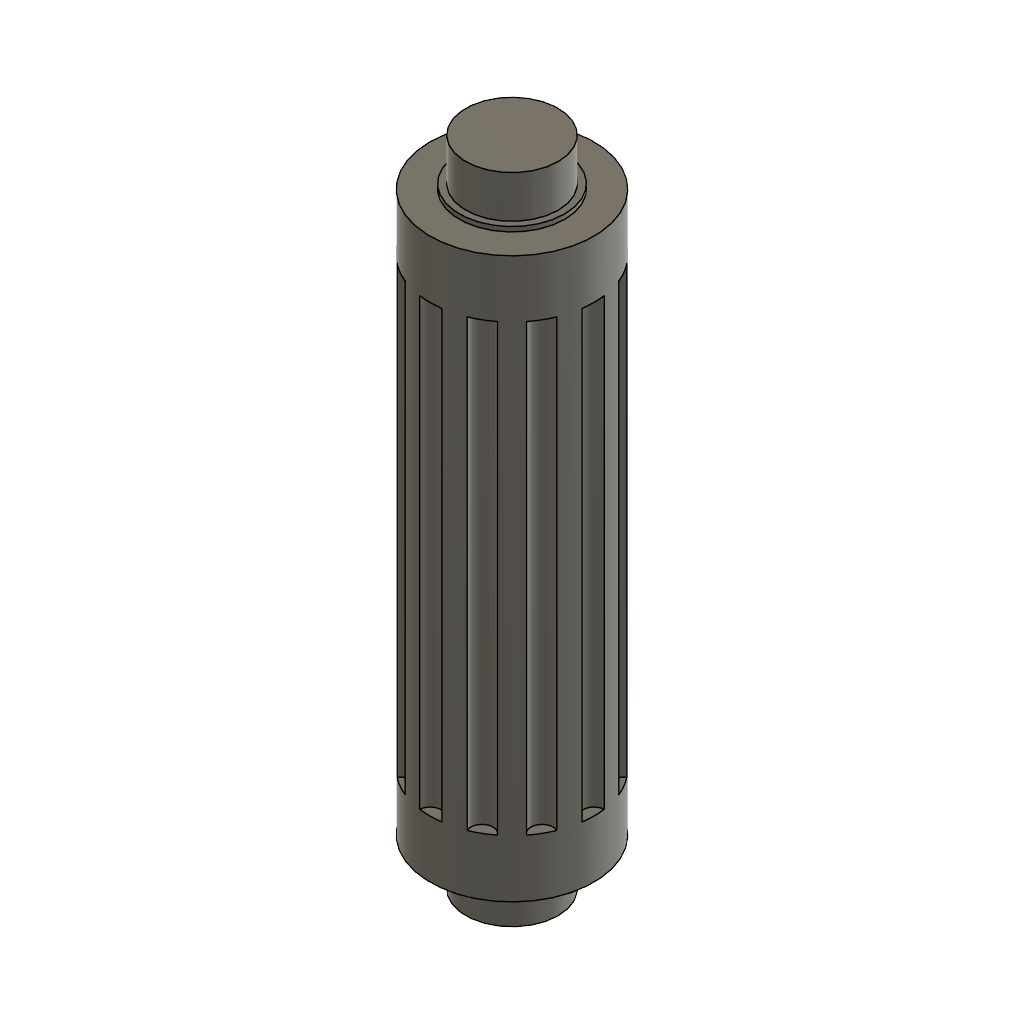
02-00_컨베이어_조립품 (Autodesk Fusion 360 archive; units mm, degrees)
design "아이들롤러"
Autodesk Fusion 360 part; units mm, degrees
(part 1 of 2)
sketch "스케치1" plane through (0, 0, 0) normal (0, 1, 0) x (1, 0, 0)
  circle A0 centre (0, 0) radius 7
  dimension "d1" = 14
  constraint coincident A0.centre origin
  measures "d1" diameter of A0
extrude "돌출1" add sketch "스케치1" along normal blind 47.8
sketch "스케치2" plane through (0, 47.8, 0) normal (0, 1, 0) x (-1, 0, 0)
  circle A0 centre (0, 0) radius 7
  circle A1 centre (0, 0) radius 4.5
  dimension "d4" = 9
  constraint coincident A0.centre A1.centre
  measures "d4" diameter of A1
extrude "돌출2" add sketch "스케치2" along normal blind 0.4 contours A1
sketch "스케치3" plane through (0, 48.2, 0) normal (0, 1, 0) x (-1, 0, 0)
  circle A0 centre (0, 0) radius 4.5
  circle A1 centre (0, 0) radius 3.95
  dimension "d7" = 7.9
  constraint coincident A0.centre A1.centre
  measures "d7" diameter of A1
extrude "돌출3" add sketch "스케치3" along normal blind 3.6 contours A1
sketch "스케치4" plane through (0, 0, 0) normal (0, -1, 0) x (1, 0, 0)
  circle A0 centre (0, 0) radius 7
  circle A1 centre (0, 0) radius 4.5
  dimension "d10" = 9
  constraint concentric A0 A1
  measures "d10" diameter of A1
extrude "돌출4" add sketch "스케치4" along normal blind 0.4 contours A1
sketch "스케치5" plane through (0, -0.4, 0) normal (0, -1, 0) x (1, 0, 0)
  circle A0 centre (0, 0) radius 4.5
  circle A1 centre (0, 0) radius 3.95
  dimension "d13" = 7.9
  constraint coincident A0.centre A1.centre
  measures "d13" diameter of A1
extrude "돌출5" add sketch "스케치5" along normal blind 3.6 contours A1
ref_plane "작업 평면1" through (0, 4.9, 0) normal (0, -1, 0) x (-1, 0, 0)
sketch "스케치6" plane through (0, 4.9, 0) normal (0, -1, 0) x (-1, 0, 0)
  circle A0 centre (-7, 0) radius 0.95
  circle A1 centre (-6.0622, -3.5) radius 0.95
  circle A2 centre (-3.5, -6.0622) radius 0.95
  circle A3 centre (0, -7) radius 0.95
  circle A4 centre (3.5, -6.0622) radius 0.95
  circle A5 centre (6.0622, -3.5) radius 0.95
  circle A6 centre (7, 0) radius 0.95
  circle A7 centre (6.0622, 3.5) radius 0.95
  circle A8 centre (3.5, 6.0622) radius 0.95
  circle A9 centre (0, 7) radius 0.95
  circle A10 centre (-3.5, 6.0622) radius 0.95
  circle A11 centre (-6.0622, 3.5) radius 0.95
  dimension "d18" = 1.9
  dimension "d20" = 360
  measures "d18" diameter of A0
extrude "돌출6" cut sketch "스케치6" against normal blind 38

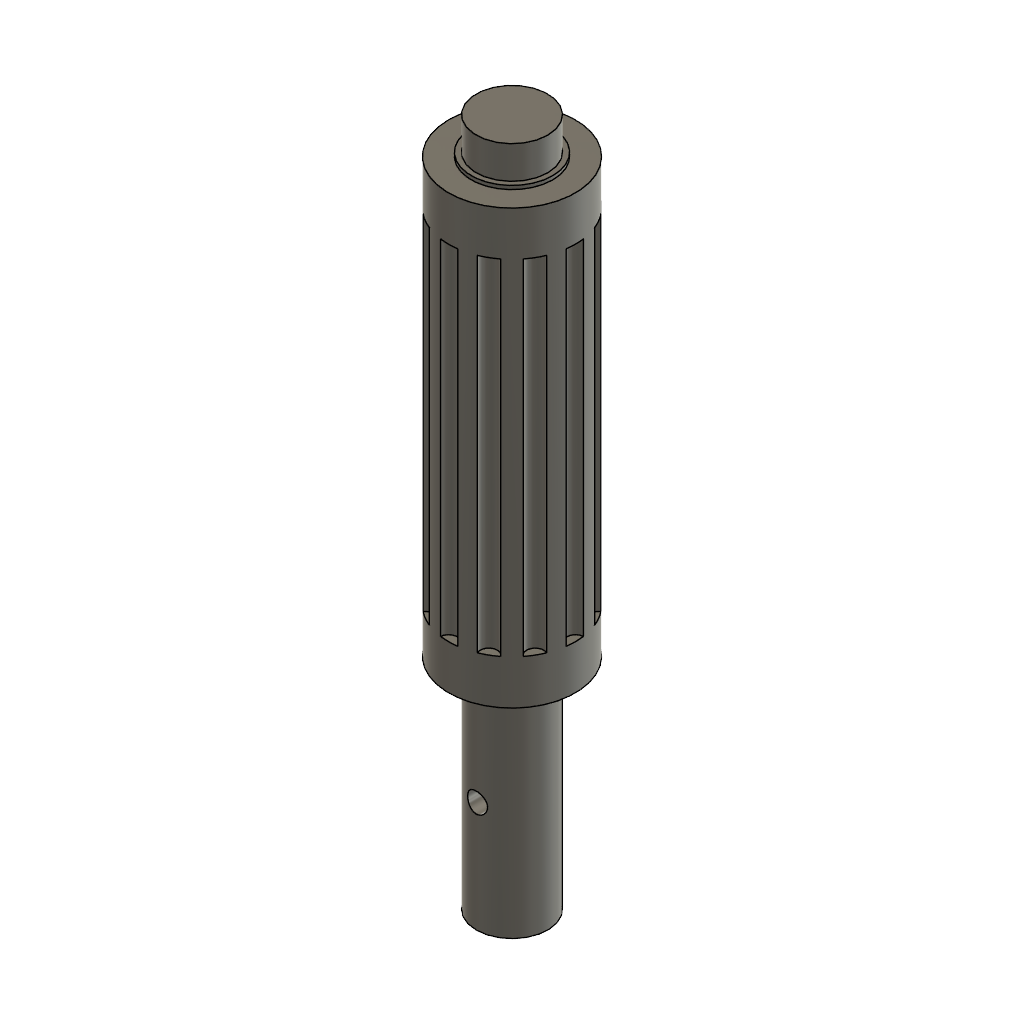
design "구동롤러"
Autodesk Fusion 360 part; units mm, degrees
sketch "스케치1" plane through (0, 0, 0) normal (0, 1, 0) x (1, 0, 0)
  circle A0 centre (0, 0) radius 7
  dimension "d1" = 14
  constraint coincident A0.centre origin
  measures "d1" diameter of A0
extrude "돌출1" add sketch "스케치1" along normal blind 47.8
sketch "스케치2" plane through (0, 47.8, 0) normal (0, 1, 0) x (-1, 0, 0)
  circle A0 centre (0, 0) radius 7
  circle A1 centre (0, 0) radius 4.5
  dimension "d4" = 9
  constraint coincident A0.centre A1.centre
  measures "d4" diameter of A1
extrude "돌출2" add sketch "스케치2" along normal blind 0.4 contours A1
sketch "스케치3" plane through (0, 0, 0) normal (0, -1, 0) x (1, 0, 0)
  circle A0 centre (0, 0) radius 7
  circle A1 centre (0, 0) radius 4.5
  dimension "d7" = 9
  constraint concentric A0 A1
  measures "d7" diameter of A1
extrude "돌출3" add sketch "스케치3" along normal blind 0.4 contours A1
sketch "스케치4" plane through (0, -0.4, 0) normal (0, -1, 0) x (1, 0, 0)
  circle A0 centre (0, 0) radius 4.5
  circle A1 centre (0, 0) radius 3.95
  dimension "d10" = 7.9
  constraint concentric A0 A1
  measures "d10" diameter of A1
extrude "돌출4" add sketch "스케치4" along normal blind 23.8 contours A1
sketch "스케치5" plane through (0, 48.2, 0) normal (0, 1, 0) x (-1, 0, 0)
  circle A0 centre (0, 0) radius 4.5
  circle A1 centre (0, 0) radius 3.95
  dimension "d13" = 7.9
  constraint concentric A0 A1
  measures "d13" diameter of A1
extrude "돌출5" add sketch "스케치5" along normal blind 3.6 contours A1
ref_plane "작업 평면1" through (0, 42.9, 0) normal (0, 1, 0) x (1, 0, 0)
sketch "스케치6" plane through (0, 42.9, 0) normal (0, 1, 0) x (1, 0, 0)
  circle A0 centre (7, 0) radius 0.95
  circle A1 centre (6.0622, 3.5) radius 0.95
  circle A2 centre (3.5, 6.0622) radius 0.95
  circle A3 centre (0, 7) radius 0.95
  circle A4 centre (-3.5, 6.0622) radius 0.95
  circle A5 centre (-6.0622, 3.5) radius 0.95
  circle A6 centre (-7, 0) radius 0.95
  circle A7 centre (-6.0622, -3.5) radius 0.95
  circle A8 centre (-3.5, -6.0622) radius 0.95
  circle A9 centre (0, -7) radius 0.95
  circle A10 centre (3.5, -6.0622) radius 0.95
  circle A11 centre (6.0622, -3.5) radius 0.95
  dimension "d18" = 1.9
  dimension "d20" = 360
  measures "d18" diameter of A0
extrude "돌출6" cut sketch "스케치6" against normal blind 38
sketch "스케치7" plane through (0, -24.2, 0) normal (0, -1, 0) x (1, 0, 0)
  circle A0 centre (0, 0) radius 3.95
  line L0 (2.5695, -3) -> (-2.5695, -3)
  dimension "d23" = 3
  constraint coincident A0 L0.start
  constraint coincident A0 L0.end
  constraint horizontal L0
  measures "d23" distance of A0.centre L0
extrude "돌출7" cut sketch "스케치7" against normal blind 23.8 contours A0 L0 picked at (0.7068, -3.1109)
sketch "스케치8" plane through (0, 0, -3) normal (0, 0, -1) x (-1, 0, 0)
  line L0 (-2.5695, -24.2) -> (2.5695, -24.2)
  line L1 (2.5695, -24.2) -> (2.5695, -0.4)
  line L2 (2.5695, -0.4) -> (-2.5695, -0.4)
  line L3 (-2.5695, -0.4) -> (-2.5695, -24.2)
  circle A0 centre (0, -12) radius 1.1
  dimension "d26" = 2.2
  dimension "d27" = 12.2
  measures "d26" diameter of A0
  measures "d27" distance of L0 A0.centre
extrude "돌출8" cut sketch "스케치8" against normal blind 7 contours A0

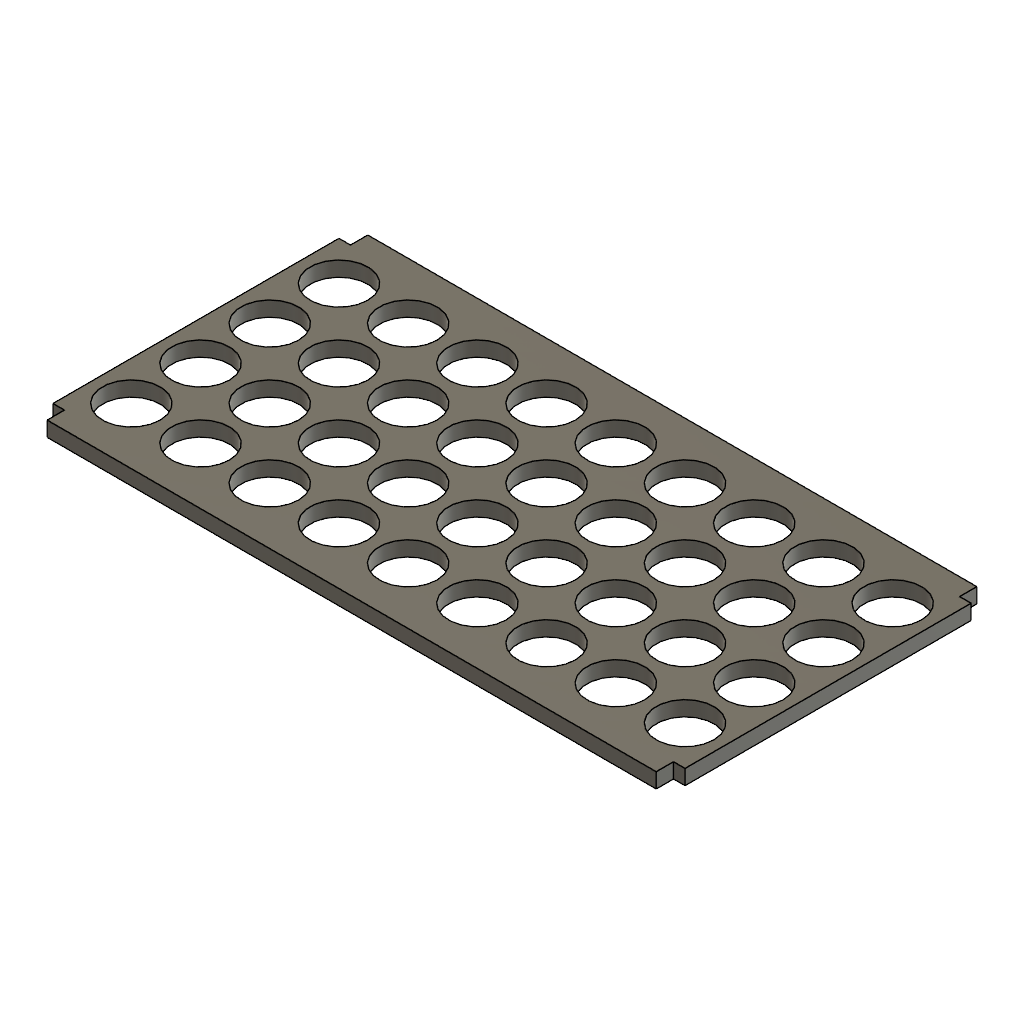
design "받침판"
Autodesk Fusion 360 part; units mm, degrees
sketch "스케치1" plane through (0, 0, 0) normal (0, 1, 0) x (1, 0, 0)
  line L0 (-54.8, 27.8) -> (54.8, 27.8)
  line L1 (54.8, 27.8) -> (54.8, -27.8)
  line L2 (54.8, -27.8) -> (-54.8, -27.8)
  line L3 (-54.8, -27.8) -> (-54.8, 27.8)
  line L4 (0, 27.8) -> (0, -27.8) construction
  line L5 (-54.8, 0) -> (54.8, 0) construction
  dimension "d1" = 109.6
  dimension "d3" = 55.6
  constraint horizontal L0
  constraint vertical L1
  constraint horizontal L2
  constraint vertical L3
  constraint midpoint L0 L4.start
  constraint midpoint L2 L4.end
  constraint midpoint L3 L5.start
  constraint midpoint L1 L5.end
  constraint coincident origin L4
  constraint coincident origin L5
  measures "d1" distance of L0.start L0.end
  measures "d3" distance of L0.end L1.end
extrude "돌출1" add sketch "스케치1" along normal blind 2.6
sketch "스케치2" plane through (0, 2.6, 0) normal (0, 1, 0) x (-1, 0, 0)
  line L0 (54.8, 27.8) -> (-54.8, 27.8)
  line L1 (-54.8, 27.8) -> (-54.8, -27.8)
  line L2 (-54.8, -27.8) -> (54.8, -27.8)
  line L3 (54.8, -27.8) -> (54.8, 27.8)
  line L4 (-54.8, -27.8) -> (-52.8, -27.8)
  line L5 (-52.8, -27.8) -> (-52.8, -24.8)
  line L6 (-52.8, -24.8) -> (-54.8, -24.8)
  line L7 (-54.8, -24.8) -> (-54.8, -27.8)
  line L8 (-54.8, 27.8) -> (-52.8, 27.8)
  line L9 (-52.8, 27.8) -> (-52.8, 24.8)
  line L10 (-52.8, 24.8) -> (-54.8, 24.8)
  line L11 (-54.8, 24.8) -> (-54.8, 27.8)
  line L12 (54.8, 27.8) -> (52.8, 27.8)
  line L13 (52.8, 27.8) -> (52.8, 24.8)
  line L14 (52.8, 24.8) -> (54.8, 24.8)
  line L15 (54.8, 24.8) -> (54.8, 27.8)
  line L16 (54.8, -27.8) -> (52.8, -27.8)
  line L17 (52.8, -27.8) -> (52.8, -24.8)
  line L18 (52.8, -24.8) -> (54.8, -24.8)
  line L19 (54.8, -24.8) -> (54.8, -27.8)
  dimension "d6" = 2
  dimension "d7" = 3
  dimension "d8" = 2
  dimension "d9" = 3
  dimension "d10" = 2
  dimension "d11" = 3
  dimension "d12" = 2
  dimension "d13" = 3
  constraint horizontal L4
  constraint vertical L5
  constraint horizontal L6
  constraint vertical L7
  constraint coincident L1.end L2.start
  constraint horizontal L8
  constraint vertical L9
  constraint horizontal L10
  constraint vertical L11
  constraint coincident L0.end L1.start
  constraint horizontal L12
  constraint vertical L13
  constraint horizontal L14
  constraint vertical L15
  constraint coincident L0.start L3.end
  constraint horizontal L16
  constraint vertical L17
  constraint horizontal L18
  constraint vertical L19
  constraint coincident L2.end L3.start
  measures "d6" distance of L1.end L4.end
  measures "d7" distance of L1.end L6.end
  measures "d8" distance of L0.end L8.end
  measures "d9" distance of L0.end L10.end
  measures "d10" distance of L0.start L12.end
  measures "d11" distance of L0.start L14.end
  measures "d12" distance of L2.end L16.end
  measures "d13" distance of L2.end L18.end
extrude "돌출2" cut sketch "스케치2" against normal blind 2.6 contours L0 L3 L12 L13 L14 L15 | L0 L1 L8 L9 L10 L11 | L2 L3 L16 L17 L18 L19 | L1 L2 L4 L5 L6 L7
sketch "스케치3" plane through (0, 2.6, 0) normal (0, 1, 0) x (-1, 0, 0)
  line L0 (52.8, -27.8) -> (52.8, -24.8)
  line L1 (52.8, -24.8) -> (54.8, -24.8)
  line L2 (54.8, -24.8) -> (54.8, 24.8)
  line L3 (54.8, 24.8) -> (52.8, 24.8)
  line L4 (52.8, 24.8) -> (52.8, 27.8)
  line L5 (52.8, 27.8) -> (-52.8, 27.8)
  line L6 (-52.8, 27.8) -> (-52.8, 24.8)
  line L7 (-52.8, 24.8) -> (-54.8, 24.8)
  line L8 (-54.8, 24.8) -> (-54.8, -24.8)
  line L9 (-54.8, -24.8) -> (-52.8, -24.8)
  line L10 (-52.8, -24.8) -> (-52.8, -27.8)
  line L11 (-52.8, -27.8) -> (52.8, -27.8)
  circle A0 centre (-48, -18) radius 5
  circle A1 centre (-36, -18) radius 5
  circle A2 centre (-24, -18) radius 5
  circle A3 centre (-12, -18) radius 5
  circle A4 centre (0, -18) radius 5
  circle A5 centre (12, -18) radius 5
  circle A6 centre (24, -18) radius 5
  circle A7 centre (36, -18) radius 5
  circle A8 centre (48, -18) radius 5
  circle A9 centre (-48, -6) radius 5
  circle A10 centre (-36, -6) radius 5
  circle A11 centre (-24, -6) radius 5
  circle A12 centre (-12, -6) radius 5
  circle A13 centre (0, -6) radius 5
  circle A14 centre (12, -6) radius 5
  circle A15 centre (24, -6) radius 5
  circle A16 centre (36, -6) radius 5
  circle A17 centre (48, -6) radius 5
  circle A18 centre (-48, 6) radius 5
  circle A19 centre (-36, 6) radius 5
  circle A20 centre (-24, 6) radius 5
  circle A21 centre (-12, 6) radius 5
  circle A22 centre (0, 6) radius 5
  circle A23 centre (12, 6) radius 5
  circle A24 centre (24, 6) radius 5
  circle A25 centre (36, 6) radius 5
  circle A26 centre (48, 6) radius 5
  circle A27 centre (-48, 18) radius 5
  circle A28 centre (-36, 18) radius 5
  circle A29 centre (-24, 18) radius 5
  circle A30 centre (-12, 18) radius 5
  circle A31 centre (0, 18) radius 5
  circle A32 centre (12, 18) radius 5
  circle A33 centre (24, 18) radius 5
  circle A34 centre (36, 18) radius 5
  circle A35 centre (48, 18) radius 5
  dimension "d16" = 10
  dimension "d19" = 96
  dimension "d20" = 36
  dimension "d21" = 6.8
  dimension "d22" = 9.8
  measures "d16" diameter of A0
  measures "d21" distance of L8 A0.centre
  measures "d22" distance of L11 A0.centre
extrude "돌출3" cut sketch "스케치3" against normal blind 2.6 contours A0 | A1 | A2 | A3 | A4 | A5 | A6 | A7 | A8 | A9 | A10 | A11 | A12 | A13 | A14 | A15 | A16 | A17 | A18 | A19 | A20 | A21 | A22 | A23 | A24 | A25 | A26 | A27 | A28 | A29 | A30 | A31 | A32 | A33 | A34 | A35

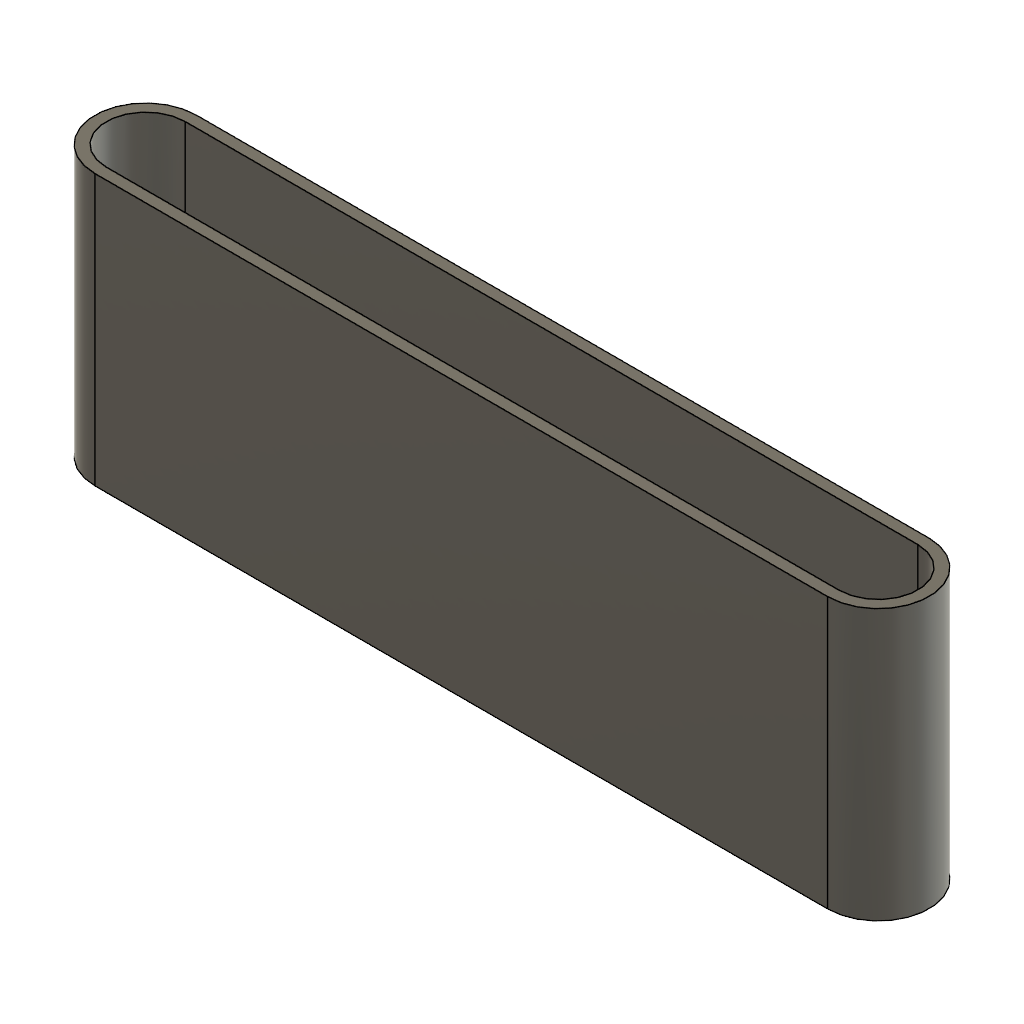
design "벨트"
Autodesk Fusion 360 part; units mm, degrees
sketch "스케치1" plane through (0, 0, 0) normal (0, 1, 0) x (1, 0, 0)
  line L0 (-65, -9) -> (65, -9)
  arc A0 (65, -9) -> (65, 9) centre (65, 0) ccw
  line L1 (65, 9) -> (-65, 9)
  arc A1 (-65, 9) -> (-65, -9) centre (-65, 0) ccw
  line L2 (-65, 0) -> (65, 0) construction
  line L3 (-65, -7) -> (65, -7)
  arc A2 (65, -7) -> (65, 7) centre (65, 0) ccw
  line L4 (65, 7) -> (-65, 7)
  arc A3 (-65, 7) -> (-65, -7) centre (-65, 0) ccw
  line L5 (-65, 0) -> (65, 0) construction
  dimension "d1" = 18
  dimension "d2" = 14
  constraint tangent L0 A0
  constraint tangent A0 L1
  constraint parallel L0 L1
  constraint tangent L1 A1
  constraint tangent L0 A1
  constraint horizontal L2
  constraint midpoint origin L2
  constraint tangent L3 A2
  constraint tangent A2 L4
  constraint parallel L3 L4
  constraint tangent L4 A3
  constraint tangent L3 A3
  constraint coincident A0.centre L2.end
  constraint parallel L2 L5
  constraint coincident A1.centre L2.start
  measures "d1" diameter of A0
  measures "d2" diameter of A2
extrude "돌출1" add sketch "스케치1" along normal blind 48

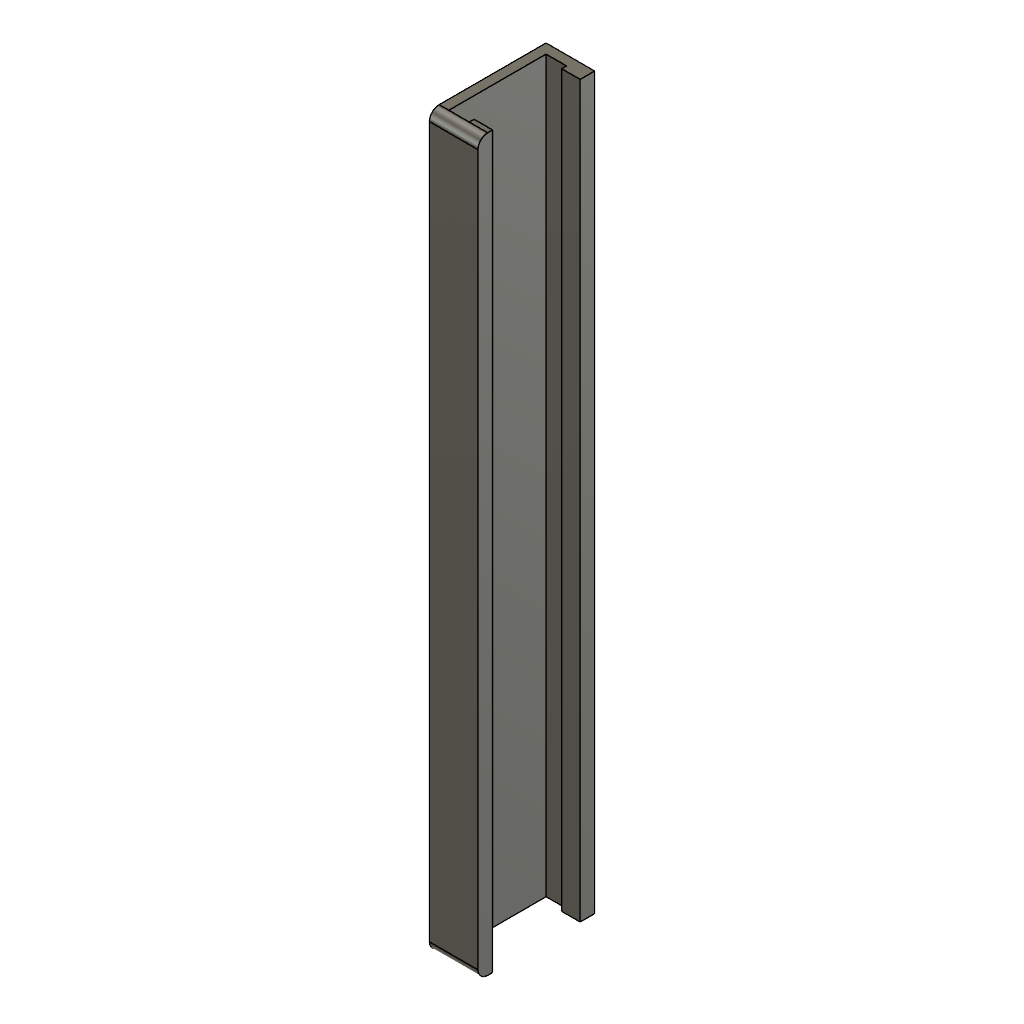
design "케이블커버"
Autodesk Fusion 360 part; units mm, degrees
sketch "스케치1" plane through (0, 0, 0) normal (0, 1, 0) x (1, 0, 0)
  line L0 (0, 0) -> (-10, 0)
  line L1 (-10, 0) -> (-10, 24)
  line L2 (-10, 24) -> (0, 24)
  line L3 (0, 24) -> (0, 21)
  line L4 (0, 21) -> (-3.8, 21)
  line L5 (-3.8, 21) -> (-3.8, 22)
  line L6 (-3.8, 22) -> (-8, 22)
  line L7 (-10, 12) -> (0, 12) construction
  line L8 (0, 0) -> (0, 3)
  line L9 (-3.8, 3) -> (-3.8, 2)
  line L10 (-3.8, 2) -> (-8, 2)
  line L11 (0, 3) -> (-3.8, 3)
  line L12 (-8, 22) -> (-8, 2)
  dimension "d1" = 10
  dimension "d2" = 24
  dimension "d3" = 3
  dimension "d4" = 3.8
  dimension "d5" = 1
  constraint coincident L0.start L8.start
  constraint horizontal L0
  constraint perpendicular L0 L1
  constraint perpendicular L1 L2
  constraint perpendicular L2 L3
  constraint perpendicular L3 L4
  constraint perpendicular L2 L5
  constraint perpendicular L5 L6
  constraint midpoint L1 L7.start
  constraint perpendicular L1 L7
  constraint symmetric L2.end L7 L0.start
  constraint symmetric L3.end L7 L8.end
  constraint symmetric L4.end L7 L9.start
  constraint symmetric L5.end L7 L9.end
  constraint symmetric L6.end L7 L10.end
  measures "d1" distance of L0.start L0.end
  measures "d2" distance of L0.end L1.end
  measures "d3" distance of L2.end L3.end
  measures "d4" distance of L3.end L4.end
  measures "d5" distance of L4.end L5.end
extrude "돌출1" add sketch "스케치1" along normal blind 150
fillet "필렛1" radius 2 2 edges at (-5, 150, 0) (-5, 0, 0)

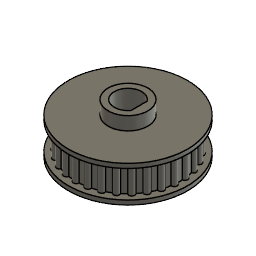
design "풀리_모터"
Autodesk Fusion 360 part; units mm, degrees
sketch "스케치1" plane through (0, 0, 0) normal (0, 1, 0) x (1, 0, 0)
  circle A0 centre (0, 0) radius 13.5
  dimension "d1" = 27
  constraint coincident A0.centre origin
  measures "d1" diameter of A0
extrude "돌출1" add sketch "스케치1" along normal blind 1
sketch "스케치2" plane through (0, 1, 0) normal (0, 1, 0) x (-1, 0, 0)
  circle A0 centre (0, 0) radius 13.5
  arc A1 (6.3702, -9.8733) -> (7.4216, -9.1095) centre (6.9065, -9.5059) ccw
  arc A2 (4.1783, -10.982) -> (5.3654, -10.4535) centre (4.7792, -10.7342) ccw
  arc A3 (1.8037, -11.6107) -> (3.0748, -11.3406) centre (2.443, -11.4932) ccw
  arc A4 (-0.6498, -11.732) -> (0.6498, -11.732) centre (0, -11.75) ccw
  arc A5 (-3.0748, -11.3406) -> (-1.8037, -11.6107) centre (-2.443, -11.4932) ccw
  arc A6 (-5.3654, -10.4535) -> (-4.1783, -10.982) centre (-4.7792, -10.7342) ccw
  arc A7 (-7.4216, -9.1095) -> (-6.3702, -9.8733) centre (-6.9065, -9.5059) ccw
  arc A8 (-9.1534, -7.3674) -> (-8.2838, -8.3331) centre (-8.732, -7.8623) ccw
  arc A9 (-10.4851, -5.3033) -> (-9.8354, -6.4287) centre (-10.1758, -5.875) ccw
  arc A10 (-11.3586, -3.0074) -> (-10.957, -4.2433) centre (-11.1749, -3.6309) ccw
  arc A11 (-11.7357, -0.5801) -> (-11.5998, -1.8725) centre (-11.6856, -1.2282) ccw
  arc A12 (-11.5998, 1.8725) -> (-11.7357, 0.5801) centre (-11.6856, 1.2282) ccw
  arc A13 (-10.957, 4.2433) -> (-11.3586, 3.0074) centre (-11.1749, 3.6309) ccw
  arc A14 (-9.8354, 6.4287) -> (-10.4851, 5.3033) centre (-10.1758, 5.875) ccw
  arc A15 (-8.2838, 8.3331) -> (-9.1534, 7.3674) centre (-8.732, 7.8623) ccw
  arc A16 (-6.3702, 9.8733) -> (-7.4216, 9.1095) centre (-6.9065, 9.5059) ccw
  arc A17 (-4.1783, 10.982) -> (-5.3654, 10.4535) centre (-4.7792, 10.7342) ccw
  arc A18 (-1.8037, 11.6107) -> (-3.0748, 11.3406) centre (-2.443, 11.4932) ccw
  arc A19 (0.6498, 11.732) -> (-0.6498, 11.732) centre (0, 11.75) ccw
  arc A20 (3.0748, 11.3406) -> (1.8037, 11.6107) centre (2.443, 11.4932) ccw
  arc A21 (5.3654, 10.4535) -> (4.1783, 10.982) centre (4.7792, 10.7342) ccw
  arc A22 (7.4216, 9.1095) -> (6.3702, 9.8733) centre (6.9065, 9.5059) ccw
  arc A23 (9.1534, 7.3674) -> (8.2838, 8.3331) centre (8.732, 7.8623) ccw
  arc A24 (10.4851, 5.3033) -> (9.8354, 6.4287) centre (10.1758, 5.875) ccw
  arc A25 (11.3586, 3.0074) -> (10.957, 4.2433) centre (11.1749, 3.6309) ccw
  arc A26 (11.7357, 0.5801) -> (11.5998, 1.8725) centre (11.6856, 1.2282) ccw
  arc A27 (11.5998, -1.8725) -> (11.7357, -0.5801) centre (11.6856, -1.2282) ccw
  arc A28 (10.957, -4.2433) -> (11.3586, -3.0074) centre (11.1749, -3.6309) ccw
  arc A29 (9.8354, -6.4287) -> (10.4851, -5.3033) centre (10.1758, -5.875) ccw
  arc A30 (8.2838, -8.3331) -> (9.1534, -7.3674) centre (8.732, -7.8623) ccw
  arc A31 (5.3654, -10.4535) -> (6.3702, -9.8733) centre (0, 0) ccw
  arc A32 (3.0748, -11.3406) -> (4.1783, -10.982) centre (0, 0) ccw
  arc A33 (0.6498, -11.732) -> (1.8037, -11.6107) centre (0, 0) ccw
  arc A34 (-1.8037, -11.6107) -> (-0.6498, -11.732) centre (0, 0) ccw
  arc A35 (-4.1783, -10.982) -> (-3.0748, -11.3406) centre (0, 0) ccw
  arc A36 (-6.3702, -9.8733) -> (-5.3654, -10.4535) centre (0, 0) ccw
  arc A37 (-8.2838, -8.3331) -> (-7.4216, -9.1095) centre (0, 0) ccw
  arc A38 (-9.8354, -6.4287) -> (-9.1534, -7.3674) centre (0, 0) ccw
  arc A39 (-10.957, -4.2433) -> (-10.4851, -5.3033) centre (0, 0) ccw
  arc A40 (-11.5998, -1.8725) -> (-11.3586, -3.0074) centre (0, 0) ccw
  arc A41 (-11.7357, 0.5801) -> (-11.7357, -0.5801) centre (0, 0) ccw
  arc A42 (-11.3586, 3.0074) -> (-11.5998, 1.8725) centre (0, 0) ccw
  arc A43 (-10.4851, 5.3033) -> (-10.957, 4.2433) centre (0, 0) ccw
  arc A44 (-9.1534, 7.3674) -> (-9.8354, 6.4287) centre (0, 0) ccw
  arc A45 (-7.4216, 9.1095) -> (-8.2838, 8.3331) centre (0, 0) ccw
  arc A46 (-5.3654, 10.4535) -> (-6.3702, 9.8733) centre (0, 0) ccw
  arc A47 (-3.0748, 11.3406) -> (-4.1783, 10.982) centre (0, 0) ccw
  arc A48 (-0.6498, 11.732) -> (-1.8037, 11.6107) centre (0, 0) ccw
  arc A49 (1.8037, 11.6107) -> (0.6498, 11.732) centre (0, 0) ccw
  arc A50 (4.1783, 10.982) -> (3.0748, 11.3406) centre (0, 0) ccw
  arc A51 (6.3702, 9.8733) -> (5.3654, 10.4535) centre (0, 0) ccw
  arc A52 (8.2838, 8.3331) -> (7.4216, 9.1095) centre (0, 0) ccw
  arc A53 (9.8354, 6.4287) -> (9.1534, 7.3674) centre (0, 0) ccw
  arc A54 (10.957, 4.2433) -> (10.4851, 5.3033) centre (0, 0) ccw
  arc A55 (11.5998, 1.8725) -> (11.3586, 3.0074) centre (0, 0) ccw
  arc A56 (11.7357, -0.5801) -> (11.7357, 0.5801) centre (0, 0) ccw
  arc A57 (11.3586, -3.0074) -> (11.5998, -1.8725) centre (0, 0) ccw
  arc A58 (10.4851, -5.3033) -> (10.957, -4.2433) centre (0, 0) ccw
  arc A59 (7.4216, -9.1095) -> (8.2838, -8.3331) centre (0, 0) ccw
  arc A60 (9.1534, -7.3674) -> (9.8354, -6.4287) centre (0, 0) ccw
  dimension "d20" = 23.5
  dimension "d21" = 1.3
  dimension "d23" = 360
  constraint coincident A0.centre A31.centre
  constraint coincident A4.centre A34
  constraint concentric A31 A32
  constraint concentric A32 A33
  constraint concentric A33 A34
  constraint concentric A34 A35
  constraint concentric A35 A36
  constraint concentric A36 A37
  constraint concentric A37 A38
  constraint concentric A38 A39
  constraint concentric A39 A40
  constraint concentric A40 A41
  constraint concentric A41 A42
  constraint concentric A42 A43
  constraint concentric A43 A44
  constraint concentric A44 A45
  constraint concentric A45 A46
  constraint concentric A46 A47
  constraint concentric A47 A48
  constraint concentric A48 A49
  constraint concentric A49 A50
  constraint concentric A50 A51
  constraint concentric A51 A52
  constraint concentric A52 A53
  constraint concentric A53 A54
  constraint concentric A54 A55
  constraint concentric A55 A56
  constraint concentric A56 A57
  constraint concentric A57 A58
  constraint concentric A58 A60
  constraint concentric A59 A60
  measures "d20" diameter of A59
  measures "d21" diameter of A4
extrude "돌출2" add sketch "스케치2" along normal blind 6.2 contours A1 A2 A3 A4 A5 A6 A7 A8 A9 A10 A11 A12 A13 A14 A15 A16 A17 A18 A19 A20 A21 A22 A23 A24 A25 A26 A27 A28 A29 A30 A31 A32 A33 A34 A35 A36 A37 A38 A39 A40 A41 A42 A43 A44 A45 A46 A47 A48 A49 A50 A51 A52 A53 A54 A55 A56 A57 A58 A59 A60
sketch "스케치3" plane through (0, 7.2, 0) normal (0, 1, 0) x (-1, 0, 0)
  circle A0 centre (0, 0) radius 13.5
  arc A1 (9.1534, -7.3674) -> (9.8354, -6.4287) centre (0, 0) ccw
  arc A2 (9.8354, -6.4287) -> (10.4851, -5.3033) centre (10.1758, -5.875) ccw
  arc A3 (10.4851, -5.3033) -> (10.957, -4.2433) centre (0, 0) ccw
  arc A4 (10.957, -4.2433) -> (11.3586, -3.0074) centre (11.1749, -3.6309) ccw
  arc A5 (11.3586, -3.0074) -> (11.5998, -1.8725) centre (0, 0) ccw
  arc A6 (11.5998, -1.8725) -> (11.7357, -0.5801) centre (11.6856, -1.2282) ccw
  arc A7 (11.7357, -0.5801) -> (11.7357, 0.5801) centre (0, 0) ccw
  arc A8 (11.7357, 0.5801) -> (11.5998, 1.8725) centre (11.6856, 1.2282) ccw
  arc A9 (11.5998, 1.8725) -> (11.3586, 3.0074) centre (0, 0) ccw
  arc A10 (11.3586, 3.0074) -> (10.957, 4.2433) centre (11.1749, 3.6309) ccw
  arc A11 (10.957, 4.2433) -> (10.4851, 5.3033) centre (0, 0) ccw
  arc A12 (10.4851, 5.3033) -> (9.8354, 6.4287) centre (10.1758, 5.875) ccw
  arc A13 (9.8354, 6.4287) -> (9.1534, 7.3674) centre (0, 0) ccw
  arc A14 (9.1534, 7.3674) -> (8.2838, 8.3331) centre (8.732, 7.8623) ccw
  arc A15 (8.2838, 8.3331) -> (7.4216, 9.1095) centre (0, 0) ccw
  arc A16 (7.4216, 9.1095) -> (6.3702, 9.8733) centre (6.9065, 9.5059) ccw
  arc A17 (6.3702, 9.8733) -> (5.3654, 10.4535) centre (0, 0) ccw
  arc A18 (5.3654, 10.4535) -> (4.1783, 10.982) centre (4.7792, 10.7342) ccw
  arc A19 (4.1783, 10.982) -> (3.0748, 11.3406) centre (0, 0) ccw
  arc A20 (3.0748, 11.3406) -> (1.8037, 11.6107) centre (2.443, 11.4932) ccw
  arc A21 (1.8037, 11.6107) -> (0.6498, 11.732) centre (0, 0) ccw
  arc A22 (0.6498, 11.732) -> (-0.6498, 11.732) centre (0, 11.75) ccw
  arc A23 (-0.6498, 11.732) -> (-1.8037, 11.6107) centre (0, 0) ccw
  arc A24 (-1.8037, 11.6107) -> (-3.0748, 11.3406) centre (-2.443, 11.4932) ccw
  arc A25 (-3.0748, 11.3406) -> (-4.1783, 10.982) centre (0, 0) ccw
  arc A26 (-4.1783, 10.982) -> (-5.3654, 10.4535) centre (-4.7792, 10.7342) ccw
  arc A27 (-5.3654, 10.4535) -> (-6.3702, 9.8733) centre (0, 0) ccw
  arc A28 (-6.3702, 9.8733) -> (-7.4216, 9.1095) centre (-6.9065, 9.5059) ccw
  arc A29 (-7.4216, 9.1095) -> (-8.2838, 8.3331) centre (0, 0) ccw
  arc A30 (-8.2838, 8.3331) -> (-9.1534, 7.3674) centre (-8.732, 7.8623) ccw
  arc A31 (-9.1534, 7.3674) -> (-9.8354, 6.4287) centre (0, 0) ccw
  arc A32 (-9.8354, 6.4287) -> (-10.4851, 5.3033) centre (-10.1758, 5.875) ccw
  arc A33 (-10.4851, 5.3033) -> (-10.957, 4.2433) centre (0, 0) ccw
  arc A34 (-10.957, 4.2433) -> (-11.3586, 3.0074) centre (-11.1749, 3.6309) ccw
  arc A35 (-11.3586, 3.0074) -> (-11.5998, 1.8725) centre (0, 0) ccw
  arc A36 (-11.5998, 1.8725) -> (-11.7357, 0.5801) centre (-11.6856, 1.2282) ccw
  arc A37 (-11.7357, 0.5801) -> (-11.7357, -0.5801) centre (0, 0) ccw
  arc A38 (-11.7357, -0.5801) -> (-11.5998, -1.8725) centre (-11.6856, -1.2282) ccw
  arc A39 (-11.5998, -1.8725) -> (-11.3586, -3.0074) centre (0, 0) ccw
  arc A40 (-11.3586, -3.0074) -> (-10.957, -4.2433) centre (-11.1749, -3.6309) ccw
  arc A41 (-10.957, -4.2433) -> (-10.4851, -5.3033) centre (0, 0) ccw
  arc A42 (-10.4851, -5.3033) -> (-9.8354, -6.4287) centre (-10.1758, -5.875) ccw
  arc A43 (-9.8354, -6.4287) -> (-9.1534, -7.3674) centre (0, 0) ccw
  arc A44 (-9.1534, -7.3674) -> (-8.2838, -8.3331) centre (-8.732, -7.8623) ccw
  arc A45 (-8.2838, -8.3331) -> (-7.4216, -9.1095) centre (0, 0) ccw
  arc A46 (-7.4216, -9.1095) -> (-6.3702, -9.8733) centre (-6.9065, -9.5059) ccw
  arc A47 (-6.3702, -9.8733) -> (-5.3654, -10.4535) centre (0, 0) ccw
  arc A48 (-5.3654, -10.4535) -> (-4.1783, -10.982) centre (-4.7792, -10.7342) ccw
  arc A49 (-4.1783, -10.982) -> (-3.0748, -11.3406) centre (0, 0) ccw
  arc A50 (-3.0748, -11.3406) -> (-1.8037, -11.6107) centre (-2.443, -11.4932) ccw
  arc A51 (-1.8037, -11.6107) -> (-0.6498, -11.732) centre (0, 0) ccw
  arc A52 (-0.6498, -11.732) -> (0.6498, -11.732) centre (0, -11.75) ccw
  arc A53 (0.6498, -11.732) -> (1.8037, -11.6107) centre (0, 0) ccw
  arc A54 (1.8037, -11.6107) -> (3.0748, -11.3406) centre (2.443, -11.4932) ccw
  arc A55 (3.0748, -11.3406) -> (4.1783, -10.982) centre (0, 0) ccw
  arc A56 (4.1783, -10.982) -> (5.3654, -10.4535) centre (4.7792, -10.7342) ccw
  arc A57 (5.3654, -10.4535) -> (6.3702, -9.8733) centre (0, 0) ccw
  arc A58 (6.3702, -9.8733) -> (7.4216, -9.1095) centre (6.9065, -9.5059) ccw
  arc A59 (7.4216, -9.1095) -> (8.2838, -8.3331) centre (0, 0) ccw
  arc A60 (8.2838, -8.3331) -> (9.1534, -7.3674) centre (8.732, -7.8623) ccw
  dimension "d10" = 27
  constraint coincident A0.centre A1.centre
  measures "d10" diameter of A0
extrude "돌출3" add sketch "스케치3" along normal blind 1 contours A0 | A1 A2 A3 A4 A5 A6 A7 A8 A9 A10 A11 A12 A13 A14 A15 A16 A17 A18 A19 A20 A21 A22 A23 A24 A25 A26 A27 A28 A29 A30 A31 A32 A33 A34 A35 A36 A37 A38 A39 A40 A41 A42 A43 A44 A45 A46 A47 A48 A49 A50 A51 A52 A53 A54 A55 A56 A57 A58 A59 A60
sketch "스케치4" plane through (0, 8.2, 0) normal (0, 1, 0) x (-1, 0, 0)
  circle A0 centre (0, 0) radius 13.5
  circle A1 centre (0, 0) radius 4.5
  circle A2 centre (0, 0) radius 3.1
  line L0 (-2.5, -1.833) -> (-2.5, 1.833)
  dimension "d13" = 9
  dimension "d14" = 6.2
  dimension "d15" = 2.5
  constraint coincident A0.centre A1.centre
  constraint coincident A2 L0.start
  constraint coincident A2 L0.end
  constraint vertical L0
  measures "d13" diameter of A1
  measures "d14" diameter of A2
  measures "d15" distance of A0.centre L0
extrude "돌출4" cut sketch "스케치4" against normal blind 5.8 contours A2 L0 picked at (-0.6446, 0.152)
extrude "돌출5" add sketch "스케치4" along normal blind 3 contours A1 | A2 L0 picked at (-2.5774, -0.4882)
extrude "돌출6" cut 1 faces at (0.5894, 2.4, 0.7953) along direction (0, -1, 0) blind 1

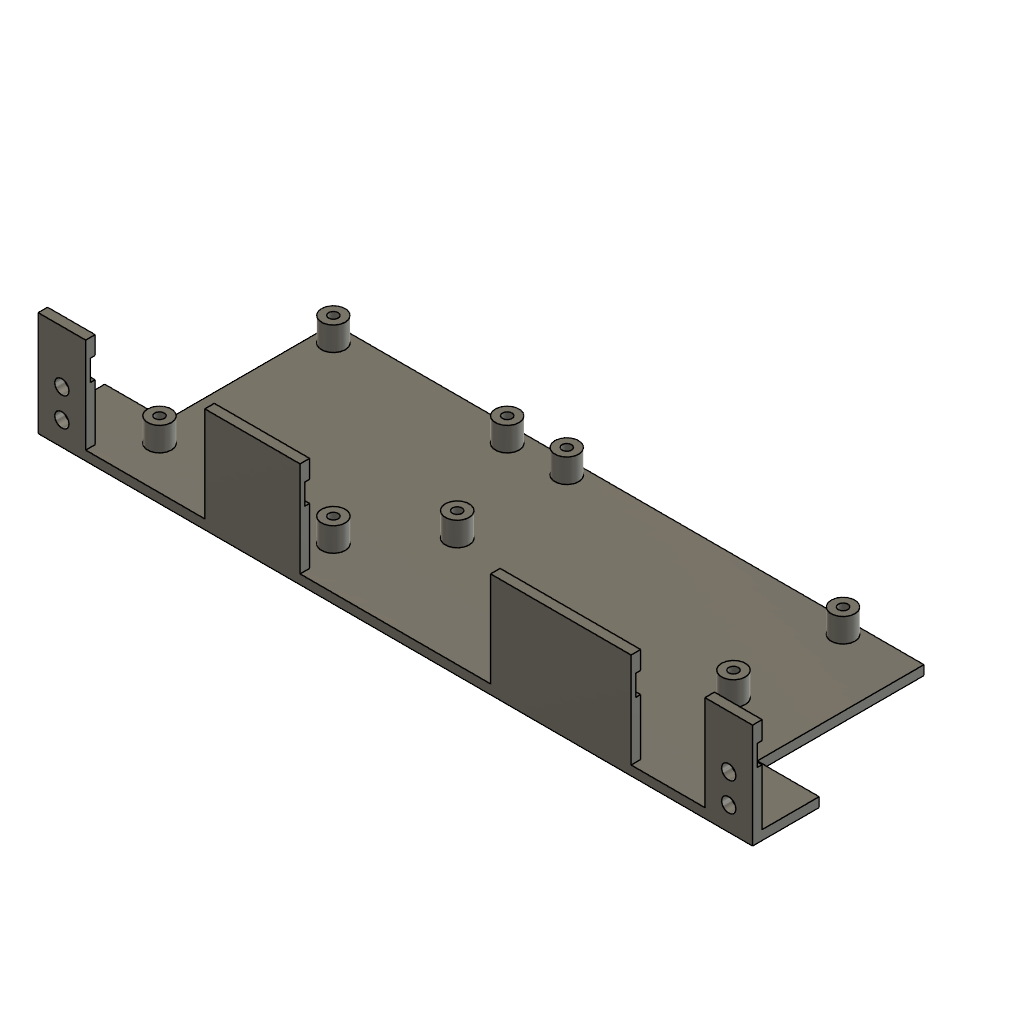
design "라즈베리파이판넬"
Autodesk Fusion 360 part; units mm, degrees
sketch "스케치1" plane through (0, 0, 0) normal (0, 1, 0) x (1, 0, 0)
  line L0 (-75, 0) -> (75, 0)
  line L1 (-75, 0) -> (-75, 14)
  line L2 (-75, 14) -> (-62, 14)
  line L3 (-62, 14) -> (-62, 49)
  line L4 (-62, 49) -> (62, 49)
  line L5 (62, 49) -> (62, 14)
  line L6 (62, 14) -> (75, 14)
  line L7 (75, 14) -> (75, 0)
  dimension "d1" = 150
  dimension "d2" = 14
  dimension "d3" = 13
  dimension "d4" = 35
  dimension "d5" = 124
  constraint horizontal L0
  constraint midpoint origin L0
  constraint perpendicular L0 L1
  constraint perpendicular L1 L2
  constraint perpendicular L0 L3
  constraint perpendicular L3 L4
  constraint perpendicular L4 L5
  constraint perpendicular L5 L6
  constraint perpendicular L0 L7
  measures "d1" distance of L0.start L0.end
  measures "d2" distance of L0.start L1.end
  measures "d3" distance of L1.end L2.end
  measures "d4" distance of L2.end L3.end
  measures "d5" distance of L3.end L4.end
extrude "돌출1" add sketch "스케치1" along normal blind 2
sketch "스케치2" plane through (0, 2, 0) normal (0, 1, 0) x (-1, 0, 0)
  line L0 (75, 0) -> (-75, 0)
  line L1 (-75, 0) -> (-75, -14)
  line L2 (-75, -14) -> (-62, -14)
  line L3 (-62, -14) -> (-62, -49)
  line L4 (-62, -49) -> (62, -49)
  line L5 (62, -49) -> (62, -14)
  line L6 (62, -14) -> (75, -14)
  line L7 (75, -14) -> (75, 0)
  line L8 (75, 0) -> (65, 0)
  line L9 (65, 0) -> (65, -2)
  line L10 (65, -2) -> (75, -2)
  line L11 (75, -2) -> (75, 0)
  line L12 (40, 0) -> (20, 0)
  line L13 (20, 0) -> (20, -2)
  line L14 (20, -2) -> (40, -2)
  line L15 (40, -2) -> (40, 0)
  line L16 (-20, 0) -> (-49.5, 0)
  line L17 (-49.5, 0) -> (-49.5, -2)
  line L18 (-49.5, -2) -> (-20, -2)
  line L19 (-20, -2) -> (-20, 0)
  line L20 (-65, 0) -> (-75, 0)
  line L21 (-75, 0) -> (-75, -2)
  line L22 (-75, -2) -> (-65, -2)
  line L23 (-65, -2) -> (-65, 0)
  dimension "d8" = 10
  dimension "d9" = 2
  dimension "d10" = 20
  dimension "d11" = 2
  dimension "d12" = 25
  dimension "d13" = 29.5
  dimension "d14" = 2
  dimension "d15" = 40
  dimension "d16" = 10
  dimension "d17" = 2
  dimension "d18" = 15.5
  constraint horizontal L8
  constraint vertical L9
  constraint horizontal L10
  constraint vertical L11
  constraint coincident L0.start L7.end
  constraint horizontal L12
  constraint vertical L13
  constraint horizontal L14
  constraint vertical L15
  constraint coincident L0 L12.start
  constraint horizontal L16
  constraint vertical L17
  constraint horizontal L18
  constraint vertical L19
  constraint coincident L0 L16.start
  constraint horizontal L20
  constraint vertical L21
  constraint horizontal L22
  constraint vertical L23
  constraint coincident L0 L20.start
  measures "d8" distance of L0.start L8.end
  measures "d9" distance of L0.start L10.end
  measures "d10" distance of L12.start L12.end
  measures "d11" distance of L12.start L14.end
  measures "d12" distance of L9 L15
  measures "d13" distance of L16.start L16.end
  measures "d14" distance of L16.start L18.end
  measures "d15" distance of L13 L19
  measures "d16" distance of L20.start L0.end
  measures "d17" distance of L20.start L22.end
  measures "d18" distance of L17 L23
extrude "돌출2" add sketch "스케치2" along normal blind 20 contours L0 L7 L8 L9 L10 L11 | L0 L12 L13 L14 L15 | L0 L16 L17 L18 L19 | L0 L1 L20 L21 L22 L23
sketch "스케치3" plane through (75, 0, 0) normal (1, 0, 0) x (0, 0, -1)
  line L0 (0, 0) -> (14, 0)
  line L1 (14, 0) -> (14, 2)
  line L2 (14, 2) -> (2, 2)
  line L3 (2, 2) -> (2, 22)
  line L4 (2, 22) -> (0, 22)
  line L5 (0, 22) -> (0, 0)
  line L6 (2, 13.8) -> (1, 13.8)
  line L7 (1, 13.8) -> (1, 18.2)
  line L8 (1, 18.2) -> (2, 18.2)
  line L9 (2, 18.2) -> (2, 13.8)
  dimension "d21" = 1
  dimension "d22" = 4.4
  dimension "d23" = 11.8
  constraint horizontal L6
  constraint vertical L7
  constraint horizontal L8
  constraint vertical L9
  constraint coincident L3 L6.start
  measures "d21" distance of L6.start L6.end
  measures "d22" distance of L6.start L8.end
  measures "d23" distance of L2 L6
extrude "돌출3" cut sketch "스케치3" against normal blind 150 contours L3 L6 L7 L8 L9
sketch "스케치4" plane through (0, 0, -2) normal (0, 0, -1) x (-1, 0, 0)
  line L0 (-65, 13.8) -> (-75, 13.8)
  line L1 (-75, 13.8) -> (-75, 2)
  line L2 (-75, 2) -> (-65, 2)
  line L3 (-65, 2) -> (-65, 13.8)
  circle A0 centre (-70, 5) radius 1.5
  circle A1 centre (-70, 11) radius 1.5
  line L4 (0, 0) -> (0, 36.3907) construction
  line L5 (75, 2) -> (65, 2)
  circle A2 centre (70, 5) radius 1.5
  line L6 (75, 13.8) -> (75, 2)
  line L7 (65, 13.8) -> (75, 13.8)
  circle A3 centre (70, 11) radius 1.5
  line L8 (65, 2) -> (65, 13.8)
  dimension "d26" = 3
  dimension "d27" = 3
  dimension "d28" = 6
  dimension "d29" = 3
  dimension "d30" = 5
  dimension "d31" = 5
  constraint coincident L4.start origin
  constraint vertical L4
  constraint symmetric L0.start L4 L7.start
  constraint symmetric L0.end L4 L6.start
  constraint symmetric L1.end L4 L5.start
  constraint symmetric L2.end L4 L5.end
  constraint symmetric A0 L4 A2
  constraint symmetric A1 L4 A3
  measures "d26" diameter of A0
  measures "d27" diameter of A1
  measures "d28" distance of A0.centre A1.centre
  measures "d29" distance of L2 A0.centre
  measures "d30" distance of L1 A0.centre
  measures "d31" distance of L1 A1.centre
extrude "돌출4" cut sketch "스케치4" against normal blind 2 contours A0 | A1 | A2 | A3
sketch "스케치5" plane through (0, 2, 0) normal (0, 1, 0) x (-1, 0, 0)
  line L0 (-65, 0) -> (-65, -2)
  line L1 (-65, -2) -> (-75, -2)
  line L2 (-75, -2) -> (-75, -14)
  line L3 (-75, -14) -> (-62, -14)
  line L4 (-62, -14) -> (-62, -49)
  line L5 (-62, -49) -> (62, -49)
  line L6 (62, -49) -> (62, -14)
  line L7 (62, -14) -> (75, -14)
  line L8 (75, -14) -> (75, -2)
  line L9 (75, -2) -> (65, -2)
  line L10 (65, -2) -> (65, 0)
  line L11 (65, 0) -> (40, 0)
  line L12 (40, 0) -> (40, -2)
  line L13 (40, -2) -> (20, -2)
  line L14 (20, -2) -> (20, 0)
  line L15 (20, 0) -> (-20, 0)
  line L16 (-20, 0) -> (-20, -2)
  line L17 (-20, -2) -> (-49.5, -2)
  line L18 (-49.5, -2) -> (-49.5, 0)
  line L19 (-49.5, 0) -> (-65, 0)
  line L20 (10, -46) -> (-48, -46) construction
  line L21 (-48, -46) -> (-48, -23) construction
  line L22 (-48, -23) -> (10, -23) construction
  line L23 (10, -23) -> (10, -46) construction
  circle A0 centre (10, -46) radius 2.5
  circle A1 centre (10, -46) radius 1
  circle A2 centre (-48, -46) radius 2.5
  circle A3 centre (-48, -46) radius 1
  circle A4 centre (-48, -23) radius 2.5
  circle A5 centre (-48, -23) radius 1
  circle A6 centre (10, -23) radius 2.5
  circle A7 centre (10, -23) radius 1
  dimension "d34" = 58
  dimension "d35" = 23
  dimension "d36" = 10
  dimension "d37" = 23
  dimension "d38" = 5
  dimension "d39" = 2
  dimension "d40" = 5
  dimension "d41" = 2
  dimension "d42" = 5
  dimension "d43" = 2
  dimension "d44" = 5
  dimension "d45" = 2
  constraint horizontal L20
  constraint vertical L21
  constraint horizontal L22
  constraint vertical L23
  constraint coincident L20.start L23.end
  constraint concentric A0 A1
  constraint coincident L20.end L21.start
  constraint concentric A2 A3
  constraint coincident L21.end L22.start
  constraint concentric A4 A5
  constraint coincident L22.end L23.start
  constraint concentric A6 A7
  measures "d34" distance of L20.start L20.end
  measures "d35" distance of L20.start L22.end
  measures "d36" distance of origin L23
  measures "d37" distance of L19 L22
  measures "d38" diameter of A0
  measures "d39" diameter of A1
  measures "d40" diameter of A2
  measures "d41" diameter of A3
  measures "d42" diameter of A4
  measures "d43" diameter of A5
  measures "d44" diameter of A6
  measures "d45" diameter of A7
extrude "돌출5" add sketch "스케치5" along normal blind 5 contours A0 | A2 | A4 | A6
sketch "스케치6" plane through (0, 2, 0) normal (0, 1, 0) x (-1, 0, 0)
  circle A0 centre (10, -46) radius 2.5
  circle A1 centre (10, -23) radius 2.5
  line L0 (-65, 0) -> (-65, -2)
  line L1 (-65, -2) -> (-75, -2)
  line L2 (-75, -2) -> (-75, -14)
  line L3 (-75, -14) -> (-62, -14)
  line L4 (-62, -14) -> (-62, -49)
  line L5 (-62, -49) -> (62, -49)
  line L6 (62, -49) -> (62, -14)
  line L7 (62, -14) -> (75, -14)
  line L8 (75, -14) -> (75, -2)
  line L9 (75, -2) -> (65, -2)
  line L10 (65, -2) -> (65, 0)
  line L11 (65, 0) -> (40, 0)
  line L12 (40, 0) -> (40, -2)
  line L13 (40, -2) -> (20, -2)
  line L14 (20, -2) -> (20, 0)
  line L15 (20, 0) -> (-20, 0)
  line L16 (-20, 0) -> (-20, -2)
  line L17 (-20, -2) -> (-49.5, -2)
  line L18 (-49.5, -2) -> (-49.5, 0)
  line L19 (-49.5, 0) -> (-65, 0)
  circle A2 centre (-48, -23) radius 2.5
  circle A3 centre (-48, -46) radius 2.5
  line L20 (58.5, -45.5) -> (22, -45.5) construction
  line L21 (22, -45.5) -> (22, -9) construction
  line L22 (22, -9) -> (58.5, -9) construction
  line L23 (58.5, -9) -> (58.5, -45.5) construction
  circle A4 centre (58.5, -45.5) radius 2.5
  circle A5 centre (58.5, -45.5) radius 1
  circle A6 centre (22, -45.5) radius 2.5
  circle A7 centre (22, -45.5) radius 1
  circle A8 centre (22, -9) radius 2.5
  circle A9 centre (22, -9) radius 1
  circle A10 centre (58.5, -9) radius 2.5
  circle A11 centre (58.5, -9) radius 1
  dimension "d48" = 36.5
  dimension "d49" = 36.5
  dimension "d50" = 9
  dimension "d51" = 22
  dimension "d52" = 5
  dimension "d53" = 2
  dimension "d54" = 5
  dimension "d55" = 2
  dimension "d56" = 5
  dimension "d57" = 2
  dimension "d58" = 5
  dimension "d59" = 2
  constraint horizontal L20
  constraint vertical L21
  constraint horizontal L22
  constraint vertical L23
  constraint coincident L20.start L23.end
  constraint concentric A4 A5
  constraint coincident L20.end L21.start
  constraint concentric A6 A7
  constraint coincident L21.end L22.start
  constraint concentric A8 A9
  constraint coincident L22.end L23.start
  constraint concentric A10 A11
  measures "d48" distance of L20.start L20.end
  measures "d49" distance of L20.start L22.end
  measures "d50" distance of L11 L22
  measures "d51" distance of origin L21
  measures "d52" diameter of A4
  measures "d53" diameter of A5
  measures "d54" diameter of A6
  measures "d55" diameter of A7
  measures "d56" diameter of A8
  measures "d57" diameter of A9
  measures "d58" diameter of A10
  measures "d59" diameter of A11
extrude "돌출6" add sketch "스케치6" along normal blind 5 contours A4 | A6 | A8 | A10
equation "d49 = d48"

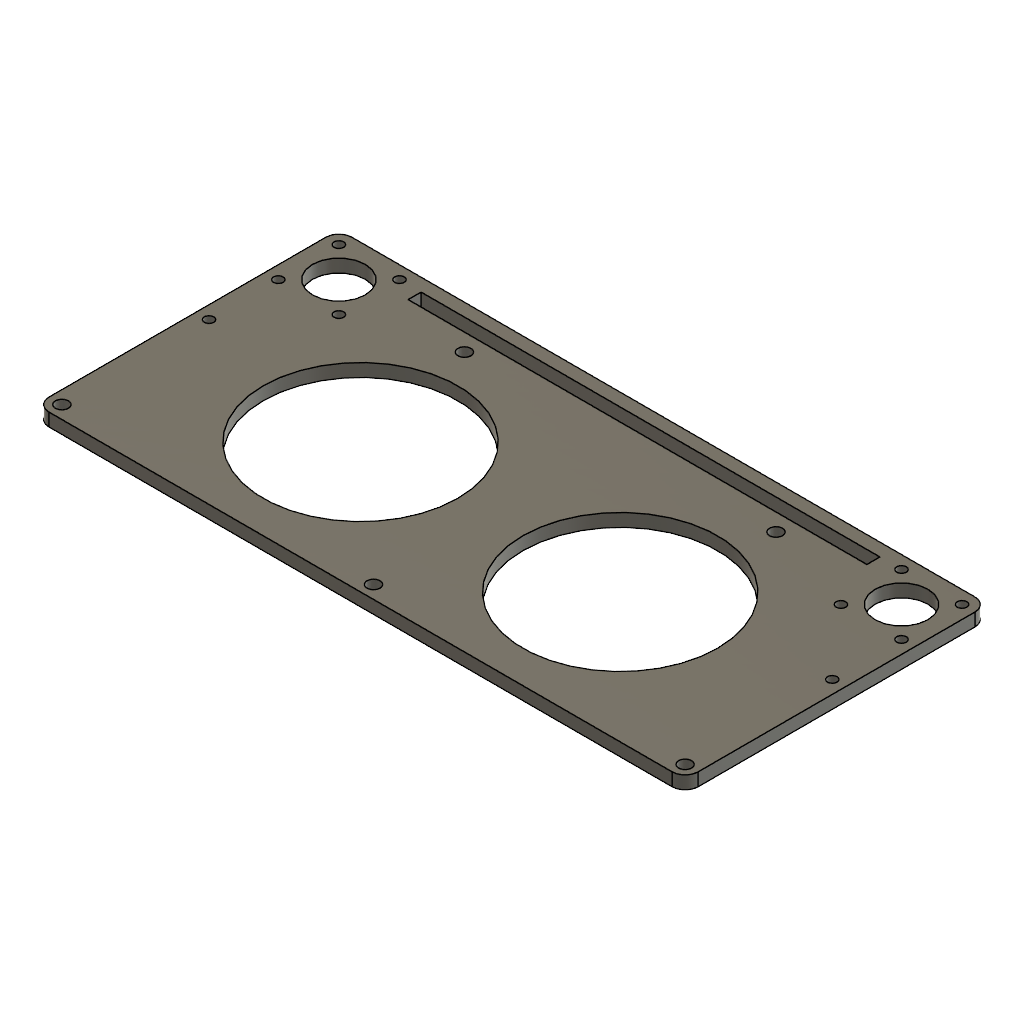
design "측판(오른쪽)"
Autodesk Fusion 360 part; units mm, degrees
sketch "스케치1" plane through (0, 0, 0) normal (0, 1, 0) x (1, 0, 0)
  line L0 (-72, 35) -> (72, 35)
  line L1 (75, 32) -> (75, -32)
  line L2 (72, -35) -> (-72, -35)
  line L3 (-75, -32) -> (-75, 32)
  line L4 (0, 35) -> (0, -35) construction
  arc A0 (-72, 35) -> (-75, 32) centre (-72, 32) ccw
  arc A1 (75, 32) -> (72, 35) centre (72, 32) ccw
  arc A2 (72, -35) -> (75, -32) centre (72, -32) ccw
  arc A3 (-75, -32) -> (-72, -35) centre (-72, -32) ccw
  circle A4 centre (-30, -5) radius 22.5
  circle A5 centre (30, -5) radius 22.5
  circle A6 centre (-65, 25) radius 6.1
  circle A7 centre (65, 25) radius 6.1
  line L5 (-53, 32) -> (53, 32)
  line L6 (53, 32) -> (53, 29)
  line L7 (53, 29) -> (-53, 29)
  line L8 (-53, 29) -> (-53, 32)
  point P0 (-75, 35)
  point P1 (75, 35)
  point P2 (75, -35)
  dimension "d1" = 150
  dimension "d2" = 70
  dimension "d3" = 3
  dimension "d4" = 45
  dimension "d5" = 45
  dimension "d6" = 5
  dimension "d7" = 5
  dimension "d8" = 30
  dimension "d9" = 60
  dimension "d10" = 12.2
  dimension "d11" = 12.2
  dimension "d12" = 25
  dimension "d13" = 25
  dimension "d14" = 130
  dimension "d15" = 10
  dimension "d16" = 106
  dimension "d17" = 3
  dimension "d18" = 3
  dimension "d19" = 22
  dimension "d20" = 75
  constraint horizontal L0
  constraint vertical L1
  constraint horizontal L2
  constraint vertical L3
  constraint midpoint origin L4
  constraint coincident L0 L4.start
  constraint coincident P0 L3
  constraint coincident P0 L0
  constraint tangent L3 A0
  constraint tangent L0 A0
  constraint coincident P1 L0
  constraint coincident P1 L1
  constraint tangent L0 A1
  constraint tangent L1 A1
  constraint equal A0 A1
  constraint coincident L2 L4.end
  constraint coincident P2 L1
  constraint coincident P2 L2
  constraint tangent L1 A2
  constraint tangent L2 A2
  constraint equal A0 A2
  constraint tangent L2 A3
  constraint tangent L3 A3
  constraint equal A0 A3
  constraint horizontal L5
  constraint vertical L6
  constraint horizontal L7
  constraint vertical L8
  measures "d1" distance of P0 P1
  measures "d2" distance of P1 P2
  measures "d3" radius of A0
  measures "d4" diameter of A4
  measures "d5" diameter of A5
  measures "d6" vertical distance of origin A4.centre
  measures "d7" vertical distance of origin A5.centre
  measures "d8" horizontal distance of origin A4.centre
  measures "d9" distance of A4.centre A5.centre
  measures "d10" diameter of A6
  measures "d11" diameter of A7
  measures "d12" vertical distance of origin A7.centre
  measures "d13" vertical distance of origin A6.centre
  measures "d14" distance of A6.centre A7.centre
  measures "d15" distance of L1 A7.centre
  measures "d16" distance of L6.end L7.end
  measures "d17" distance of L0 L5
  measures "d18" distance of L5.end L6.end
  measures "d19" distance of L3 L8
  measures "d20" distance of origin L3
extrude "돌출1" add sketch "스케치1" along normal blind 3
sketch "스케치2" plane through (0, 3, 0) normal (0, 1, 0) x (-1, 0, 0)
  circle A0 centre (-30, 5) radius 22.5
  line L0 (-53, -29) -> (53, -29)
  line L1 (53, -29) -> (53, -32)
  line L2 (53, -32) -> (-53, -32)
  line L3 (-53, -32) -> (-53, -29)
  circle A1 centre (30, 5) radius 22.5
  circle A2 centre (65, -25) radius 6.1
  circle A3 centre (-65, -25) radius 6.1
  arc A4 (72, -35) -> (75, -32) centre (72, -32) ccw
  line L4 (75, -32) -> (75, 32)
  arc A5 (75, 32) -> (72, 35) centre (72, 32) ccw
  line L5 (72, 35) -> (-72, 35)
  arc A6 (-72, 35) -> (-75, 32) centre (-72, 32) ccw
  line L6 (-75, 32) -> (-75, -32)
  arc A7 (-75, -32) -> (-72, -35) centre (-72, -32) ccw
  line L7 (-72, -35) -> (72, -35)
  circle A8 centre (36, -25) radius 1.5
  circle A9 centre (-36, -25) radius 1.5
  circle A10 centre (-72, 32) radius 1.5
  circle A11 centre (0, 32) radius 1.5
  circle A12 centre (72, 32) radius 1.5
  dimension "d23" = 3
  dimension "d24" = 3
  dimension "d25" = 3
  dimension "d26" = 3
  dimension "d27" = 3
  dimension "d28" = 72
  dimension "d29" = 25
  dimension "d30" = 25
  dimension "d31" = 39
  constraint concentric A6 A10
  constraint concentric A5 A12
  measures "d23" diameter of A8
  measures "d24" diameter of A9
  measures "d25" diameter of A10
  measures "d26" diameter of A11
  measures "d27" diameter of A12
  measures "d28" horizontal distance of A8.centre A9.centre
  measures "d29" vertical distance of origin A9.centre
  measures "d30" vertical distance of origin A8.centre
  measures "d31" distance of L4 A8.centre
extrude "돌출2" cut sketch "스케치2" against normal blind 3 contours A8 | A9 | A10 | A11 | A12
sketch "스케치3" plane through (0, 3, 0) normal (0, 1, 0) x (-1, 0, 0)
  arc A0 (72, -35) -> (75, -32) centre (72, -32) ccw
  line L0 (75, -32) -> (75, 32)
  arc A1 (75, 32) -> (72, 35) centre (72, 32) ccw
  line L1 (72, 35) -> (-72, 35)
  arc A2 (-72, 35) -> (-75, 32) centre (-72, 32) ccw
  line L2 (-75, 32) -> (-75, -32)
  arc A3 (-75, -32) -> (-72, -35) centre (-72, -32) ccw
  line L3 (-72, -35) -> (72, -35)
  circle A4 centre (-65, -25) radius 6.1
  circle A5 centre (65, -25) radius 6.1
  circle A6 centre (30, 5) radius 22.5
  line L4 (-53, -29) -> (53, -29)
  line L5 (53, -29) -> (53, -32)
  line L6 (53, -32) -> (-53, -32)
  line L7 (-53, -32) -> (-53, -29)
  circle A7 centre (-30, 5) radius 22.5
  circle A8 centre (72, 32) radius 1.5
  circle A9 centre (36, -25) radius 1.5
  circle A10 centre (0, 32) radius 1.5
  circle A11 centre (-36, -25) radius 1.5
  circle A12 centre (-72, 32) radius 1.5
  circle A13 centre (72, -32) radius 1.1
  circle A14 centre (72, -18) radius 1.1
  circle A15 centre (58, -18) radius 1.1
  circle A16 centre (58, -32) radius 1.1
  line L8 (0, -35) -> (0, 35) construction
  circle A17 centre (72, -2) radius 1.1
  circle A18 centre (-58, -32) radius 1.1
  circle A19 centre (-72, -32) radius 1.1
  circle A20 centre (-58, -18) radius 1.1
  circle A21 centre (-72, -18) radius 1.1
  circle A22 centre (-72, -2) radius 1.1
  dimension "d34" = 2.2
  dimension "d35" = 7
  dimension "d36" = 7
  dimension "d38" = 360
  dimension "d39" = 2.2
  dimension "d40" = 16
  dimension "d41" = 3
  constraint midpoint L3 L8.start
  constraint midpoint L1 L8.end
  constraint symmetric A13 L8 A19
  constraint symmetric A14 L8 A21
  constraint symmetric A15 L8 A20
  constraint symmetric A16 L8 A18
  constraint symmetric L8 A17 A22
  measures "d34" diameter of A13
  measures "d35" horizontal distance of A5.centre A0.centre
  measures "d36" vertical distance of A5.centre A0.centre
  measures "d39" diameter of A17
  measures "d40" vertical distance of A14.centre A17.centre
  measures "d41" distance of L0 A17.centre
extrude "돌출3" cut sketch "스케치3" against normal blind 3 contours A13 | A14 | A15 | A16 | A17 | A18 | A19 | A20 | A21 | A22
equation "d20 = d1 / 2"

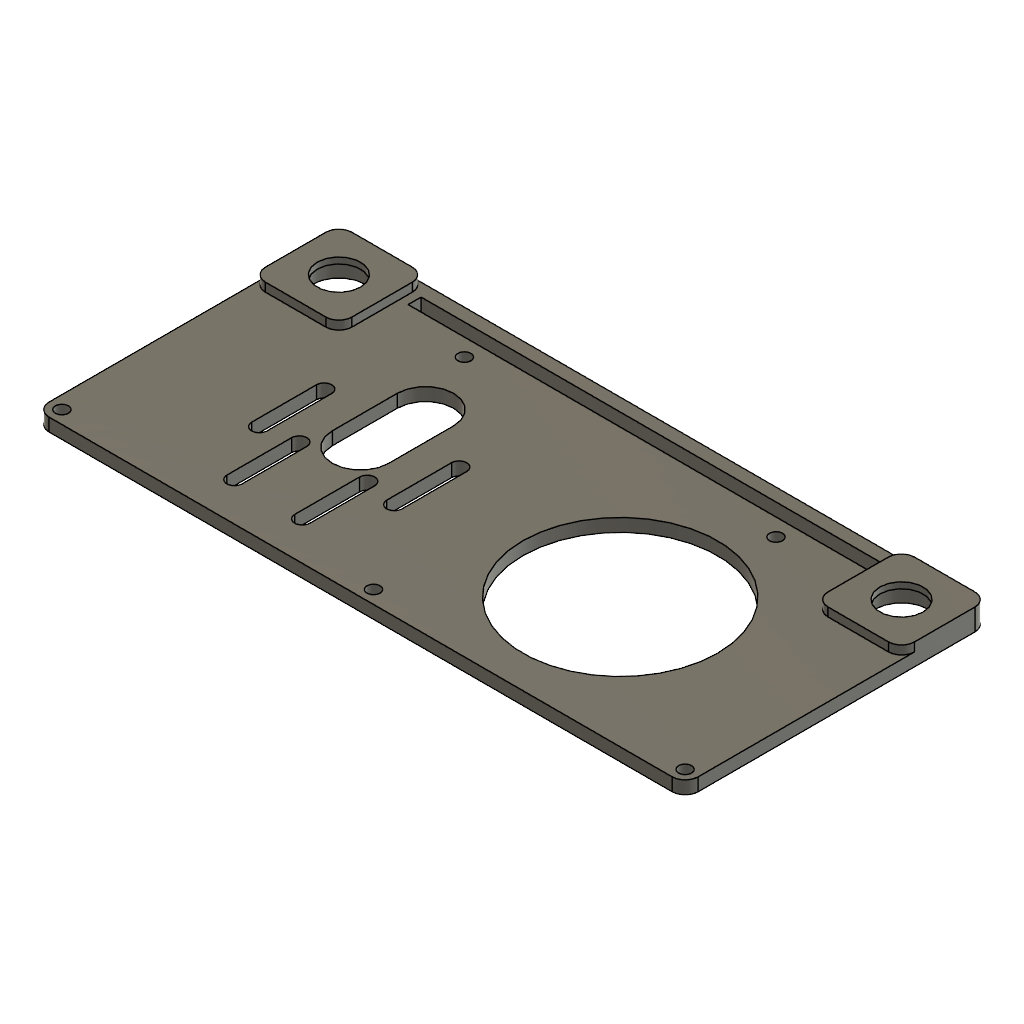
design "측판(왼쪽)"
Autodesk Fusion 360 part; units mm, degrees
sketch "스케치1" plane through (0, 0, 0) normal (0, 1, 0) x (1, 0, 0)
  line L0 (-72, 35) -> (72, 35)
  line L1 (75, 32) -> (75, -32)
  line L2 (72, -35) -> (-72, -35)
  line L3 (-75, -32) -> (-75, 32)
  line L4 (0, 35) -> (0, -35) construction
  line L5 (-75, 0) -> (75, 0) construction
  arc A0 (-72, 35) -> (-75, 32) centre (-72, 32) ccw
  arc A1 (75, 32) -> (72, 35) centre (72, 32) ccw
  arc A2 (72, -35) -> (75, -32) centre (72, -32) ccw
  arc A3 (-75, -32) -> (-72, -35) centre (-72, -32) ccw
  point P0 (-75, 35)
  point P1 (75, 35)
  point P2 (75, -35)
  dimension "d3" = 150
  dimension "d4" = 70
  dimension "d7" = 3
  constraint horizontal L0
  constraint vertical L1
  constraint horizontal L2
  constraint vertical L3
  constraint coincident origin L5
  constraint coincident origin L4
  constraint coincident L3 L5.start
  constraint coincident L0 L4.start
  constraint coincident P0 L3
  constraint coincident P0 L0
  constraint tangent L3 A0
  constraint tangent L0 A0
  constraint coincident L1 L5.end
  constraint coincident P1 L0
  constraint coincident P1 L1
  constraint tangent L0 A1
  constraint tangent L1 A1
  constraint equal A0 A1
  constraint coincident L2 L4.end
  constraint coincident P2 L1
  constraint coincident P2 L2
  constraint tangent L1 A2
  constraint tangent L2 A2
  constraint equal A0 A2
  constraint tangent L2 A3
  constraint tangent L3 A3
  constraint equal A0 A3
  measures "d3" distance of P0 P1
  measures "d4" distance of P1 P2
  measures "d7" radius of A0
extrude "돌출1" add sketch "스케치1" along normal blind 3
sketch "스케치2" plane through (0, 3, 0) normal (0, 1, 0) x (-1, 0, 0)
  arc A0 (72, -35) -> (75, -32) centre (72, -32) ccw
  line L0 (75, -32) -> (75, 32)
  arc A1 (75, 32) -> (72, 35) centre (72, 32) ccw
  line L1 (72, 35) -> (-72, 35)
  arc A2 (-72, 35) -> (-75, 32) centre (-72, 32) ccw
  line L2 (-75, 32) -> (-75, -32)
  arc A3 (-75, -32) -> (-72, -35) centre (-72, -32) ccw
  line L3 (-72, -35) -> (72, -35)
  line L4 (-72, -35) -> (-58, -35)
  line L5 (-55, -32) -> (-55, -18)
  line L6 (-58, -15) -> (-72, -15)
  line L7 (-75, -18) -> (-75, -32)
  arc A4 (-75, -32) -> (-72, -35) centre (-72, -32) ccw
  arc A5 (-72, -15) -> (-75, -18) centre (-72, -18) ccw
  arc A6 (-55, -18) -> (-58, -15) centre (-58, -18) ccw
  arc A7 (-58, -35) -> (-55, -32) centre (-58, -32) ccw
  line L8 (72, -35) -> (58, -35)
  line L9 (55, -32) -> (55, -18)
  line L10 (58, -15) -> (72, -15)
  line L11 (75, -18) -> (75, -32)
  arc A8 (72, -35) -> (75, -32) centre (72, -32) ccw
  arc A9 (55, -32) -> (58, -35) centre (58, -32) ccw
  arc A10 (58, -15) -> (55, -18) centre (58, -18) ccw
  arc A11 (75, -18) -> (72, -15) centre (72, -18) ccw
  point P0 (-75, -35)
  point P1 (-55, -35)
  point P2 (-75, -15)
  point P3 (75, -35)
  point P4 (55, -35)
  point P5 (55, -15)
  dimension "d10" = 20
  dimension "d11" = 20
  dimension "d12" = 3
  dimension "d13" = 20
  dimension "d14" = 20
  dimension "d15" = 3
  constraint horizontal L4
  constraint vertical L5
  constraint horizontal L6
  constraint vertical L7
  constraint coincident P0 L4
  constraint coincident P0 L7
  constraint tangent L4 A4
  constraint tangent L7 A4
  constraint coincident P2 L6
  constraint coincident P2 L7
  constraint tangent L6 A5
  constraint tangent L7 A5
  constraint equal A4 A5
  constraint tangent L6 A6
  constraint tangent L5 A6
  constraint equal A4 A6
  constraint coincident P1 L5
  constraint coincident P1 L4
  constraint tangent L5 A7
  constraint tangent L4 A7
  constraint equal A4 A7
  constraint horizontal L8
  constraint vertical L9
  constraint horizontal L10
  constraint vertical L11
  constraint coincident P3 L11
  constraint coincident P3 L8
  constraint tangent L11 A8
  constraint tangent L8 A8
  constraint coincident P4 L8
  constraint coincident P4 L9
  constraint tangent L8 A9
  constraint tangent L9 A9
  constraint equal A8 A9
  constraint coincident P5 L9
  constraint coincident P5 L10
  constraint tangent L9 A10
  constraint tangent L10 A10
  constraint equal A8 A10
  constraint tangent L10 A11
  constraint tangent L11 A11
  constraint equal A8 A11
  measures "d10" distance of P0 P1
  measures "d11" distance of P0 P2
  measures "d12" radius of A4
  measures "d13" distance of P3 P4
  measures "d14" distance of P4 P5
  measures "d15" radius of A8
extrude "돌출2" add sketch "스케치2" along normal blind 2 contours A0 L0 L3 L8 L9 L10 L11 A8 A9 A10 A11 | L2 A3 L3 L4 L5 L6 L7 A4 A5 A6 A7
sketch "스케치3" plane through (0, 0, 0) normal (0, -1, 0) x (1, 0, 0)
  arc A0 (-75, -32) -> (-72, -35) centre (-72, -32) ccw
  line L0 (-72, -35) -> (72, -35)
  arc A1 (72, -35) -> (75, -32) centre (72, -32) ccw
  line L1 (75, -32) -> (75, 32)
  arc A2 (75, 32) -> (72, 35) centre (72, 32) ccw
  line L2 (72, 35) -> (-72, 35)
  arc A3 (-72, 35) -> (-75, 32) centre (-72, 32) ccw
  line L3 (-75, 32) -> (-75, -32)
  circle A4 centre (65, -25) radius 6.1
  circle A5 centre (-65, -25) radius 6.1
  circle A6 centre (65, -25) radius 5
  circle A7 centre (-65, -25) radius 5
  dimension "d18" = 130
  dimension "d19" = 12.2
  dimension "d20" = 12.2
  dimension "d21" = 25
  dimension "d22" = 10
  dimension "d23" = 10
  dimension "d24" = 10
  constraint concentric A4 A6
  constraint concentric A5 A7
  measures "d18" distance of A4.centre A5.centre
  measures "d19" diameter of A4
  measures "d20" diameter of A5
  measures "d21" vertical distance of origin A5.centre
  measures "d22" distance of L1 A4.centre
  measures "d23" diameter of A6
  measures "d24" diameter of A7
extrude "돌출3" cut sketch "스케치3" against normal blind 5 contours A6 | A7
extrude "돌출4" cut sketch "스케치3" against normal blind 3.6 contours A4 | A5